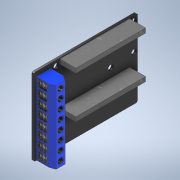
# Autodesk Inventor part: esp motor shield
Saved by Autodesk Inventor 2020 (Build 240168000, 168)
## iProperties
Created: 2021-09-14
Part Number: esp motor shield
Material: Generic
Document SubType Name: Modeling
Designer: andjil
Density: 1 g/cm^3
Appearance: Default
Author: andjil
Autodesk Inventor part; units mm, degrees
ref_plane "YZ Plane" through (0, 0, 0) normal (1, 0, 0) x (0, 1, 0)
ref_plane "XZ Plane" through (0, 0, 0) normal (0, 1, 0) x (-1, 0, 0)
ref_plane "XY Plane" through (0, 0, 0) normal (0, 0, 1) x (1, 0, 0)
sketch "Sketch1" plane through (0, 0, 0) normal (1, 0, 0) x (0, 1, 0)
  line L0 (0, 0) -> (43.1, 0)
  line L1 (43.1, 0) -> (43.1, -58)
  line L2 (43.1, -58) -> (0, -58)
  line L3 (0, -58) -> (0, 0)
  dimension "d0" = 58
  dimension "d1" = 43.1
  constraints: 8 end point, 2 parallel, 1 horizontal, 1 perpendicular
  measures "d0" distance of L0.end L1.end
  measures "d1" distance of L1.end L2.end
extrude "Extrusion1" add sketch "Sketch1" along normal blind 1.1
fillet "Fillet1" radius 1 4 edges at (0.55, 43.1, 0) (0.55, 0, 0) (0.55, 0, -58) (0.55, 43.1, -58)
sketch "Sketch2" plane through (1.1, 0, 0) normal (1, 0, 0) x (0, 0, -1)
  circle A0 centre (56, 40.1) radius 1.5
  circle A1 centre (56, 25.1) radius 1.5
  circle A2 centre (12.5, 40.1) radius 1.5
  line L0 (57, 43.1) -> (1, 43.1) projected
  line L1 (58, 1) -> (58, 42.1) projected
  line L2 (0, 42.1) -> (0, 1) projected
  circle A3 centre (43, 24.1) radius 1.5
  circle A4 centre (12.5, 12) radius 1.5
  line L3 (1, 0) -> (57, 0) projected
  point P0 (0, 0)
  dimension "d5" = 3
  dimension "d6" = 2
  dimension "d7" = 3
  dimension "d8" = 3
  dimension "d9" = 3
  dimension "d10" = 12.5
  dimension "d11" = 3
  dimension "d12" = 2
  dimension "d13" = 18
  dimension "d14" = 19
  dimension "d15" = 15
  dimension "d16" = 3
  dimension "d17" = 3
  dimension "d18" = 12
  dimension "d19" = 12.5
  constraints: 5 centre point
  measures "d5" distance from line of L0 A0.centre
  measures "d6" distance from line of L1 A0.centre
  measures "d7" diameter of A0
  measures "d8" diameter of A1
  measures "d9" diameter of A2
  measures "d10" distance from line of L2 A2.centre
  measures "d11" distance from line of L0 A2.centre
  measures "d12" distance from line of L1 A1.centre
  measures "d13" distance from line of L0 A1.centre
  measures "d14" distance from line of L0 A3.centre
  measures "d15" distance from line of L1 A3.centre
  measures "d16" diameter of A3
  measures "d17" diameter of A4
  measures "d18" distance from line of L3 A4.centre
  measures "d19" distance from line of L2 A4.centre
extrude "Extrusion2" cut sketch "Sketch2" against normal through all
sketch "Sketch3" plane through (1.1, 0, 0) normal (1, 0, 0) x (0, 0, -1)
  line L0 (14.5, 42.6) -> (53.5, 42.6)
  line L1 (53.5, 42.6) -> (53.5, 40.1)
  line L2 (53.5, 40.1) -> (14.5, 40.1)
  line L3 (14.5, 40.1) -> (14.5, 42.6)
  line L4 (57, 43.1) -> (1, 43.1) projected
  line L5 (14.5, 19.1) -> (53.5, 19.1)
  line L6 (53.5, 19.1) -> (53.5, 16.6)
  line L7 (53.5, 16.6) -> (14.5, 16.6)
  line L8 (14.5, 16.6) -> (14.5, 19.1)
  line L9 (58, 1) -> (58, 42.1) projected
  point P0 (0, 0)
  dimension "d22" = 2.5
  dimension "d23" = 39
  dimension "d24" = 0.5
  dimension "d25" = 2.5
  dimension "d26" = 21
  dimension "d27" = 39
  dimension "d28" = 4.5
  dimension "d29" = 4.5
  constraints: 16 end point, 4 parallel, 2 horizontal, 2 perpendicular
  measures "d22" distance of L2.end L0.start
  measures "d23" distance of L0.start L0.end
  measures "d24" distance between parallel lines of L4 L0
  measures "d25" distance of L7.end L5.start
  measures "d26" distance between parallel lines of L2 L5
  measures "d27" distance of L5.start L5.end
  measures "d28" distance between parallel lines of L9 L6
  measures "d29" distance between parallel lines of L9 L1
extrude "Extrusion3" add sketch "Sketch3" along normal blind 9
sketch "Sketch4" plane through (1.1, 0, 0) normal (1, 0, 0) x (0, 0, -1)
  line L0 (1.5, 40.6) -> (9.5, 40.6)
  line L1 (9.5, 40.6) -> (9.5, 0.2)
  line L2 (9.5, 0.2) -> (1.5, 0.2)
  line L3 (1.5, 0.2) -> (1.5, 40.6)
  line L4 (57, 43.1) -> (1, 43.1) projected
  line L5 (1, 0) -> (57, 0) projected
  line L6 (0, 42.1) -> (0, 1) projected
  point P0 (0, 0)
  dimension "d32" = 2.5
  dimension "d33" = 0.2
  dimension "d34" = 1.5
  dimension "d35" = 8
  constraints: 8 end point, 2 parallel, 1 horizontal, 1 perpendicular
  measures "d32" distance between parallel lines of L4 L0
  measures "d33" distance between parallel lines of L5 L2
  measures "d34" distance between parallel lines of L6 L3
  measures "d35" distance of L0.start L0.end
extrude "Extrusion4" add sketch "Sketch4" along normal blind 10
chamfer "Chamfer1" distance 1 distance2 3 1 edges at (11.1, 20.4, -1.5) measured on face at (11.1, 27.1333, -4.1667)
chamfer "Chamfer2" distance 2 distance2 3 1 edges at (11.1, 20.4, -9.5) measured on face at (11.1, 27.1333, -4.8333)
sketch "Sketch5" plane through (11.1, 0, 0) normal (1, 0, 0) x (0, 0, -1)
  line L0 (1.5, 40.6) -> (9.5, 40.6) projected
  line L1 (5, 40.6) -> (5, 0.2) construction
  line L2 (9.5, 0.2) -> (1.5, 0.2) projected
  line L3 (2.5, 0.2) -> (2.5, 40.6) projected
  circle A0 centre (5, 38.1256) radius 1.5
  circle A1 centre (5, 33.1256) radius 1.5
  circle A2 centre (5, 28.1256) radius 1.5
  circle A3 centre (5, 23.1256) radius 1.5
  circle A4 centre (5, 18.1256) radius 1.5
  circle A5 centre (5, 13.1256) radius 1.5
  circle A6 centre (5, 8.1256) radius 1.5
  circle A7 centre (5, 3.1256) radius 1.5
  point P0 (0, 0)
  dimension "d44" = 2.5
  dimension "d45" = 3
  dimension "d48" = 5
  constraints: 8 centre point, 3 point on line, 2 end point, 2 vertical, 14 other
  measures "d44" distance between parallel lines of L3 L1
  measures "d45" diameter of A0
  measures "d48" distance of A0.centre A1.centre
extrude "Extrusion5" cut sketch "Sketch5" against normal blind 2
sketch "Sketch6" plane through (1.1, 0.2, -1.5) normal (0, 0, 1) x (1, 0, 0)
  line L0 (6, 39.9) -> (1, 39.9)
  line L1 (1, 39.9) -> (1, 35.9)
  line L2 (1, 35.9) -> (6, 35.9)
  line L3 (6, 35.9) -> (6, 39.9)
  line L4 (0, 40.4) -> (7, 40.4) projected
  line L5 (0, 41.9) -> (0, 0.8) projected
  line L6 (6, 30.9) -> (6, 34.9)
  line L7 (6, 34.9) -> (1, 34.9)
  line L8 (1, 30.9) -> (6, 30.9)
  line L9 (1, 34.9) -> (1, 30.9)
  line L10 (6, 25.9) -> (6, 29.9)
  line L11 (6, 29.9) -> (1, 29.9)
  line L12 (1, 25.9) -> (6, 25.9)
  line L13 (1, 29.9) -> (1, 25.9)
  line L14 (6, 20.9) -> (6, 24.9)
  line L15 (6, 24.9) -> (1, 24.9)
  line L16 (1, 20.9) -> (6, 20.9)
  line L17 (1, 24.9) -> (1, 20.9)
  line L18 (6, 15.9) -> (6, 19.9)
  line L19 (6, 19.9) -> (1, 19.9)
  line L20 (1, 15.9) -> (6, 15.9)
  line L21 (1, 19.9) -> (1, 15.9)
  line L22 (6, 10.9) -> (6, 14.9)
  line L23 (6, 14.9) -> (1, 14.9)
  line L24 (1, 10.9) -> (6, 10.9)
  line L25 (1, 14.9) -> (1, 10.9)
  line L26 (6, 5.9) -> (6, 9.9)
  line L27 (6, 9.9) -> (1, 9.9)
  line L28 (1, 5.9) -> (6, 5.9)
  line L29 (1, 9.9) -> (1, 5.9)
  line L30 (6, 0.9) -> (6, 4.9)
  line L31 (6, 4.9) -> (1, 4.9)
  line L32 (1, 0.9) -> (6, 0.9)
  line L33 (1, 4.9) -> (1, 0.9)
  point P0 (-1.1, -0.2)
  dimension "d55" = 5
  dimension "d56" = 4
  dimension "d57" = 0.5
  dimension "d58" = 1
  dimension "d61" = 5
  constraints: 64 end point, 2 parallel, 1 horizontal, 1 perpendicular, 1 vertical, 56 other
  measures "d55" distance of L0.start L0.end
  measures "d56" distance of L0.end L1.end
  measures "d57" distance between parallel lines of L4 L0
  measures "d58" distance between parallel lines of L5 L1
  measures "d61" distance of L2.end L6.start
extrude "Extrusion6" cut sketch "Sketch6" against normal blind 1
sketch "Sketch7" plane through (0, 0, 0) normal (-1, 0, 0) x (0, 0, 1)
  circle A0 centre (-5, 38.1256) radius 1.5 projected
  circle A1 centre (-5, 3.1256) radius 1.5 projected
  line L0 (-5, 38.1256) -> (-5, 3.1256) construction
  line L1 (-5.5, 38.6256) -> (-4.5, 38.6256)
  line L2 (-4.5, 38.6256) -> (-4.5, 37.6256)
  line L3 (-4.5, 37.6256) -> (-5.5, 37.6256)
  line L4 (-5.5, 37.6256) -> (-5.5, 38.6256)
  line L5 (-5.5, 38.6256) -> (-4.5, 37.6256) construction
  line L6 (-4.5, 38.6256) -> (-5.5, 37.6256) construction
  line L7 (-5.5, 33.6256) -> (-4.5, 33.6256)
  line L8 (-5.5, 32.6256) -> (-5.5, 33.6256)
  line L9 (-4.5, 32.6256) -> (-5.5, 32.6256)
  line L10 (-4.5, 33.6256) -> (-4.5, 32.6256)
  line L11 (-5.5, 28.6256) -> (-4.5, 28.6256)
  line L12 (-5.5, 27.6256) -> (-5.5, 28.6256)
  line L13 (-4.5, 27.6256) -> (-5.5, 27.6256)
  line L14 (-4.5, 28.6256) -> (-4.5, 27.6256)
  line L15 (-5.5, 23.6256) -> (-4.5, 23.6256)
  line L16 (-5.5, 22.6256) -> (-5.5, 23.6256)
  line L17 (-4.5, 22.6256) -> (-5.5, 22.6256)
  line L18 (-4.5, 23.6256) -> (-4.5, 22.6256)
  line L19 (-5.5, 18.6256) -> (-4.5, 18.6256)
  line L20 (-5.5, 17.6256) -> (-5.5, 18.6256)
  line L21 (-4.5, 17.6256) -> (-5.5, 17.6256)
  line L22 (-4.5, 18.6256) -> (-4.5, 17.6256)
  line L23 (-5.5, 13.6256) -> (-4.5, 13.6256)
  line L24 (-5.5, 12.6256) -> (-5.5, 13.6256)
  line L25 (-4.5, 12.6256) -> (-5.5, 12.6256)
  line L26 (-4.5, 13.6256) -> (-4.5, 12.6256)
  line L27 (-5.5, 8.6256) -> (-4.5, 8.6256)
  line L28 (-5.5, 7.6256) -> (-5.5, 8.6256)
  line L29 (-4.5, 7.6256) -> (-5.5, 7.6256)
  line L30 (-4.5, 8.6256) -> (-4.5, 7.6256)
  line L31 (-5.5, 3.6256) -> (-4.5, 3.6256)
  line L32 (-5.5, 2.6256) -> (-5.5, 3.6256)
  line L33 (-4.5, 2.6256) -> (-5.5, 2.6256)
  line L34 (-4.5, 3.6256) -> (-4.5, 2.6256)
  point P0 (0, 0)
  dimension "d68" = 1
  dimension "d69" = 1
  dimension "d72" = 5
  constraints: 70 end point, 2 midpoint, 2 parallel, 2 vertical, 1 horizontal, 1 perpendicular, 56 other
  measures "d68" distance of L1.start L1.end
  measures "d69" distance of L1.end L2.end
  measures "d72" distance of L1.start L7.start
extrude "Extrusion7" add sketch "Sketch7" along normal blind 4 contours L1 L2 L3 L4 | L7 L10 L9 L8 | L11 L14 L13 L12 | L15 L18 L17 L16 | L19 L22 L21 L20 | L23 L26 L25 L24 | L27 L30 L29 L28 | L31 L34 L33 L32
sketch "Sketch8" plane through (0, 0, 0) normal (-1, 0, 0) x (0, 0, 1)
  line L0 (-53.5, 42.6) -> (-53.5, 40.1) projected
  line L1 (-53.5, 41.6495) -> (-14.5, 41.6495)
  line L2 (-14.5, 40.1) -> (-14.5, 42.6) projected
  line L3 (-53.5, 19.1) -> (-53.5, 16.6) projected
  line L4 (-53.5, 17.85) -> (-14.5, 17.85)
  line L5 (-14.5, 16.6) -> (-14.5, 19.1) projected
  line L6 (-56.597, 1.5) -> (-20.7107, 1.5) construction
  line L7 (-1, 0) -> (-57, 0) projected
  line L8 (-57, 2) -> (-56, 2)
  line L9 (-56, 2) -> (-56, 1)
  line L10 (-56, 1) -> (-57, 1)
  line L11 (-57, 1) -> (-57, 2)
  line L12 (-57, 2) -> (-56, 1) construction
  line L13 (-56, 2) -> (-57, 1) construction
  line L14 (-58, 1) -> (-58, 42.1) projected
  line L15 (-54, 2) -> (-53, 2)
  line L16 (-54, 1) -> (-54, 2)
  line L17 (-53, 1) -> (-54, 1)
  line L18 (-53, 2) -> (-53, 1)
  line L19 (-51, 2) -> (-50, 2)
  line L20 (-51, 1) -> (-51, 2)
  line L21 (-50, 1) -> (-51, 1)
  line L22 (-50, 2) -> (-50, 1)
  line L23 (-48, 2) -> (-47, 2)
  line L24 (-48, 1) -> (-48, 2)
  line L25 (-47, 1) -> (-48, 1)
  line L26 (-47, 2) -> (-47, 1)
  line L27 (-45, 2) -> (-44, 2)
  line L28 (-45, 1) -> (-45, 2)
  line L29 (-44, 1) -> (-45, 1)
  line L30 (-44, 2) -> (-44, 1)
  line L31 (-42, 2) -> (-41, 2)
  line L32 (-42, 1) -> (-42, 2)
  line L33 (-41, 1) -> (-42, 1)
  line L34 (-41, 2) -> (-41, 1)
  line L35 (-39, 2) -> (-38, 2)
  line L36 (-39, 1) -> (-39, 2)
  line L37 (-38, 1) -> (-39, 1)
  line L38 (-38, 2) -> (-38, 1)
  line L39 (-36, 2) -> (-35, 2)
  line L40 (-36, 1) -> (-36, 2)
  line L41 (-35, 1) -> (-36, 1)
  line L42 (-35, 2) -> (-35, 1)
  line L43 (-33, 2) -> (-32, 2)
  line L44 (-33, 1) -> (-33, 2)
  line L45 (-32, 1) -> (-33, 1)
  line L46 (-32, 2) -> (-32, 1)
  line L47 (-30, 2) -> (-29, 2)
  line L48 (-30, 1) -> (-30, 2)
  line L49 (-29, 1) -> (-30, 1)
  line L50 (-29, 2) -> (-29, 1)
  line L51 (-27, 2) -> (-26, 2)
  line L52 (-27, 1) -> (-27, 2)
  line L53 (-26, 1) -> (-27, 1)
  line L54 (-26, 2) -> (-26, 1)
  line L55 (-57, 5) -> (-56, 5)
  line L56 (-57, 4) -> (-57, 5)
  line L57 (-56, 4) -> (-57, 4)
  line L58 (-56, 5) -> (-56, 4)
  line L59 (-54, 5) -> (-53, 5)
  line L60 (-54, 4) -> (-54, 5)
  line L61 (-53, 4) -> (-54, 4)
  line L62 (-53, 5) -> (-53, 4)
  line L63 (-51, 5) -> (-50, 5)
  line L64 (-51, 4) -> (-51, 5)
  line L65 (-50, 4) -> (-51, 4)
  line L66 (-50, 5) -> (-50, 4)
  line L67 (-48, 5) -> (-47, 5)
  line L68 (-48, 4) -> (-48, 5)
  line L69 (-47, 4) -> (-48, 4)
  line L70 (-47, 5) -> (-47, 4)
  line L71 (-45, 5) -> (-44, 5)
  line L72 (-45, 4) -> (-45, 5)
  line L73 (-44, 4) -> (-45, 4)
  line L74 (-44, 5) -> (-44, 4)
  line L75 (-42, 5) -> (-41, 5)
  line L76 (-42, 4) -> (-42, 5)
  line L77 (-41, 4) -> (-42, 4)
  line L78 (-41, 5) -> (-41, 4)
  line L79 (-39, 5) -> (-38, 5)
  line L80 (-39, 4) -> (-39, 5)
  line L81 (-38, 4) -> (-39, 4)
  line L82 (-38, 5) -> (-38, 4)
  line L83 (-36, 5) -> (-35, 5)
  line L84 (-36, 4) -> (-36, 5)
  line L85 (-35, 4) -> (-36, 4)
  line L86 (-35, 5) -> (-35, 4)
  line L87 (-33, 5) -> (-32, 5)
  line L88 (-33, 4) -> (-33, 5)
  line L89 (-32, 4) -> (-33, 4)
  line L90 (-32, 5) -> (-32, 4)
  line L91 (-30, 5) -> (-29, 5)
  line L92 (-30, 4) -> (-30, 5)
  line L93 (-29, 4) -> (-30, 4)
  line L94 (-29, 5) -> (-29, 4)
  line L95 (-27, 5) -> (-26, 5)
  line L96 (-27, 4) -> (-27, 5)
  line L97 (-26, 4) -> (-27, 4)
  line L98 (-26, 5) -> (-26, 4)
  line L99 (-57, 8) -> (-56, 8)
  line L100 (-57, 7) -> (-57, 8)
  line L101 (-56, 7) -> (-57, 7)
  line L102 (-56, 8) -> (-56, 7)
  line L103 (-54, 8) -> (-53, 8)
  line L104 (-54, 7) -> (-54, 8)
  line L105 (-53, 7) -> (-54, 7)
  line L106 (-53, 8) -> (-53, 7)
  line L107 (-51, 8) -> (-50, 8)
  line L108 (-51, 7) -> (-51, 8)
  line L109 (-50, 7) -> (-51, 7)
  line L110 (-50, 8) -> (-50, 7)
  line L111 (-48, 8) -> (-47, 8)
  line L112 (-48, 7) -> (-48, 8)
  line L113 (-47, 7) -> (-48, 7)
  line L114 (-47, 8) -> (-47, 7)
  line L115 (-45, 8) -> (-44, 8)
  line L116 (-45, 7) -> (-45, 8)
  line L117 (-44, 7) -> (-45, 7)
  line L118 (-44, 8) -> (-44, 7)
  line L119 (-42, 8) -> (-41, 8)
  line L120 (-42, 7) -> (-42, 8)
  line L121 (-41, 7) -> (-42, 7)
  line L122 (-41, 8) -> (-41, 7)
  line L123 (-39, 8) -> (-38, 8)
  line L124 (-39, 7) -> (-39, 8)
  line L125 (-38, 7) -> (-39, 7)
  line L126 (-38, 8) -> (-38, 7)
  line L127 (-36, 8) -> (-35, 8)
  line L128 (-36, 7) -> (-36, 8)
  line L129 (-35, 7) -> (-36, 7)
  line L130 (-35, 8) -> (-35, 7)
  line L131 (-33, 8) -> (-32, 8)
  line L132 (-33, 7) -> (-33, 8)
  line L133 (-32, 7) -> (-33, 7)
  line L134 (-32, 8) -> (-32, 7)
  line L135 (-30, 8) -> (-29, 8)
  line L136 (-30, 7) -> (-30, 8)
  line L137 (-29, 7) -> (-30, 7)
  line L138 (-29, 8) -> (-29, 7)
  line L139 (-27, 8) -> (-26, 8)
  line L140 (-27, 7) -> (-27, 8)
  line L141 (-26, 7) -> (-27, 7)
  line L142 (-26, 8) -> (-26, 7)
  point P0 (0, 0)
  point P1 (-56.5, 1.5)
  dimension "d79" = 1.5
  dimension "d82" = 1
  dimension "d83" = 1
  dimension "d84" = 1
  dimension "d87" = 3
  dimension "d90" = 3
  constraints: 274 end point, 4 horizontal, 4 midpoint, 3 point on line, 2 parallel, 1 perpendicular, 1 vertical, 256 other
  measures "d79" distance between parallel lines of L7 L6
  measures "d82" distance of L8.start L8.end
  measures "d83" distance of L8.end L9.end
  measures "d84" distance between parallel lines of L14 L11
  measures "d87" distance of L8.start L15.start
  measures "d90" distance of L8.start L55.start
extrude "Extrusion8" add sketch "Sketch8" along normal blind 3
body "Solid1"
